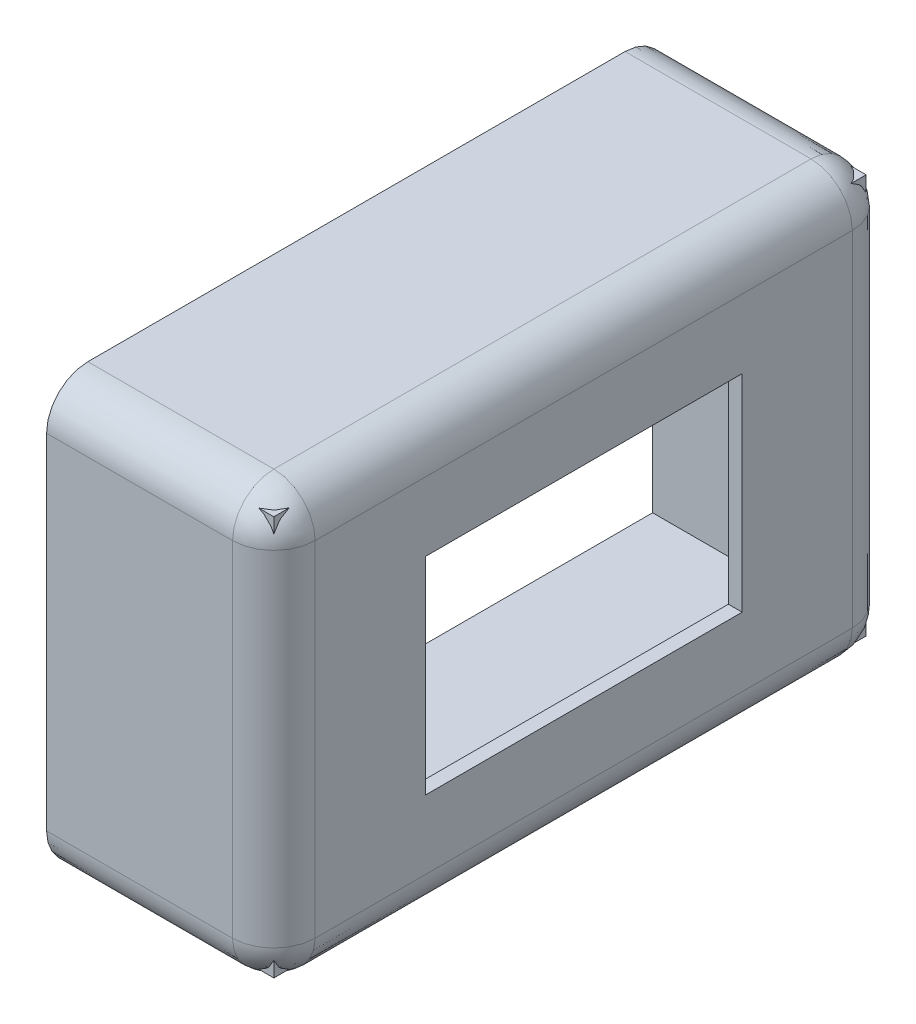
# Autodesk Inventor part: Watch pt1
Saved by Autodesk Inventor 2026.1 (Build 301233000, 233)
## iProperties
Created: 2026-04-08
Part Number: Watch pt1
Material: Generic
Document SubType Name: Modeling
Designer: abinav.valluri65
Density: 1 g/cm^3
Appearance: Default
Author: abinav.valluri65
Autodesk Inventor part; units mm, degrees
ref_plane "YZ Plane" through (0, 0, 0) normal (1, 0, 0) x (0, 1, 0)
ref_plane "XZ Plane" through (0, 0, 0) normal (0, 1, 0) x (-1, 0, 0)
ref_plane "XY Plane" through (0, 0, 0) normal (0, 0, 1) x (1, 0, 0)
sketch "Sketch1" plane through (0, 0, 0) normal (1, 0, 0) x (0, 1, 0)
  line L0 (245.116, 809.4898) -> (276.116, 809.4898)
  line L1 (245.116, 809.4898) -> (245.116, 764.4898)
  line L2 (245.116, 764.4898) -> (276.116, 764.4898)
  line L3 (276.116, 809.4898) -> (276.116, 764.4898)
  point P0 (0, 0)
  dimension "d1" = 31
  dimension "d2" = 45
  dimension "d3" = 31
  constraints: 8 end point, 1 horizontal, 1 perpendicular, 1 vertical
  measures "d1" distance of L0.start L0.end
  measures "d2" distance of L0.start L1.end
  measures "d3" distance of L1.end L2.end
extrude "Extrusion1" add sketch "Sketch1" along normal blind 16.5
sketch "Sketch2" plane through (16.5, 0, 0) normal (1, 0, 0) x (0, 0, -1)
  line L0 (-766.4898, 276.116) -> (-807.4898, 276.116)
  line L1 (-809.4898, 276.116) -> (-809.4898, 273.116)
  line L2 (-809.4898, 274.116) -> (-809.4898, 247.116)
  line L3 (-809.4898, 245.116) -> (-809.4898, 248.116)
  line L4 (-809.4898, 276.116) -> (-807.4898, 276.116)
  line L5 (-807.4898, 245.116) -> (-766.4898, 245.116)
  line L6 (-764.4898, 276.116) -> (-766.4898, 276.116)
  line L7 (-764.4898, 247.116) -> (-764.4898, 274.116)
  line L8 (-764.4898, 276.116) -> (-764.4898, 273.116)
  line L9 (-798.4898, 268.116) -> (-798.4898, 253.116)
  line L10 (-798.4898, 253.116) -> (-775.4898, 253.116)
  line L11 (-775.4898, 253.116) -> (-775.4898, 268.116)
  line L12 (-775.4898, 268.116) -> (-798.4898, 268.116)
  line L13 (-809.4898, 245.116) -> (-764.4898, 245.116) projected
  line L14 (-809.4898, 245.116) -> (-764.4898, 245.116)
  point P0 (0, 0)
  point P1 (-786.9898, 260.616)
  point P2 (-786.9898, 260.616)
  point P3 (-786.9898, 260.616)
  dimension "d13" = 15
  dimension "d14" = 23
  constraints: 28 end point, 11 point on line, 1 coincident, 1 collinear
  measures "d13" distance of L9.start L9.end
  measures "d14" distance of L9.end L10.end
shell "Shell1" thickness 1 removed faces 1 at (0, 265.7826, 779.4898)
sketch "Sketch3" plane through (16.5, 0, 0) normal (1, 0, 0) x (0, 0, -1)
  point P0 (0, 0)
sketch "Sketch4" plane through (16.5, 0, 0) normal (1, 0, 0) x (0, 0, -1)
  point P0 (0, 0)
fillet "Fillet2" radius 3 8 edges at (16.5, 260.616, 764.4898) (16.5, 276.116, 786.9898) (16.5, 245.116, 786.9898) (16.5, 260.616, 809.4898) (8.25, 276.116, 764.4898) (8.25, 245.116, 764.4898) (8.25, 276.116, 809.4898) (8.25, 245.116, 809.4898)
extrude "Extrusion2" cut sketch "Sketch2" against normal blind 16.5
sketch "Sketch5" plane through (16.5, 253.116, 798.4898) normal (0, 0, -1) x (-1, 0, 0)
  point P0 (16.5, -253.116)
body "Solid1"
